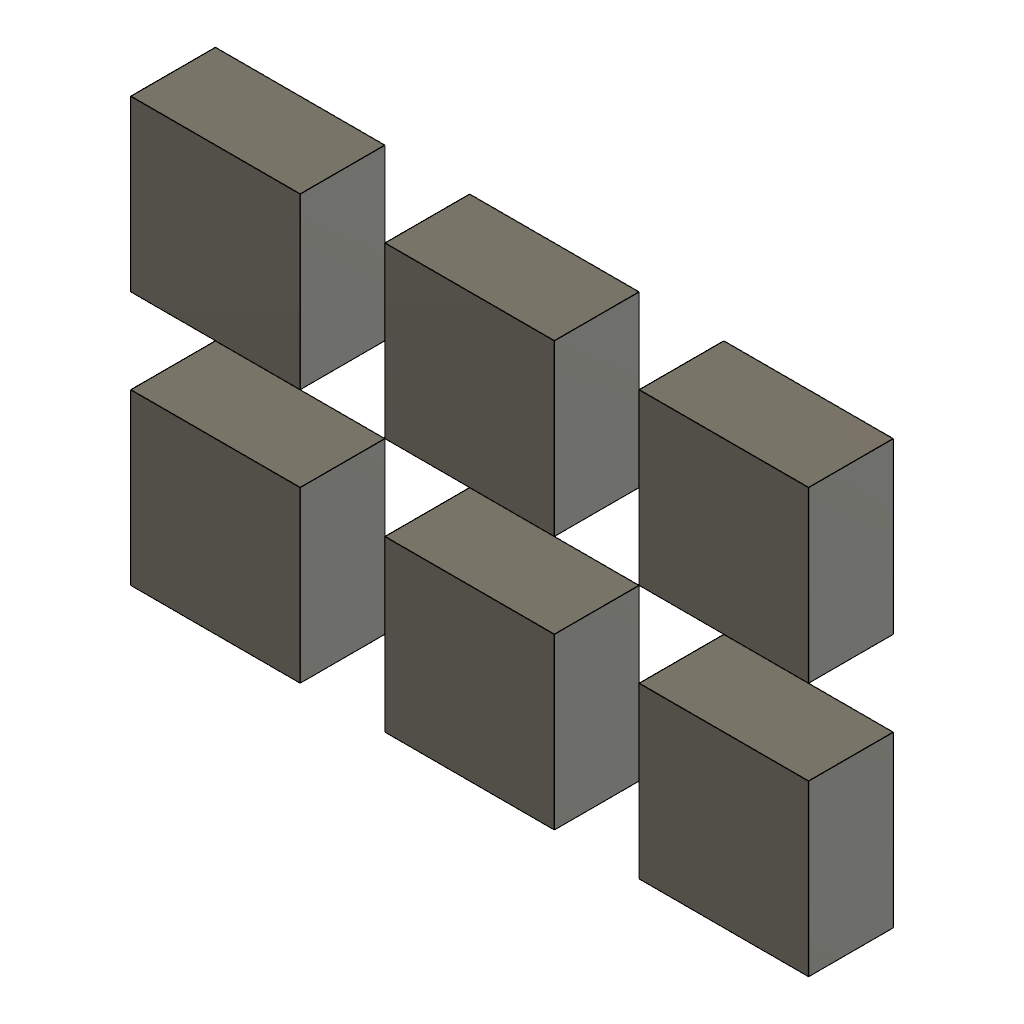
pat_rect_bodies (Autodesk Fusion 360 design; units mm, degrees)
part number: 2026-11-13-14-43-53-146
Autodesk Fusion 360 part; units mm, degrees
sketch "Sketch1" plane through (0, 0, 0) normal (0, 0, 1) x (1, 0, 0)
  line L0 (0, 0) -> (10, 0)
  line L1 (10, 0) -> (10, 10)
  line L2 (10, 10) -> (0, 10)
  line L3 (0, 10) -> (0, 0)
extrude "Extrude1" add sketch "Sketch1" along normal blind 5 makes body 1
pattern_linear "R-Pattern1" count 3 spacing 15 along (1, 0, 0) count 2 spacing 15 along (0, 1, 0) of bodies 1 makes body 2 at (18.3333, 6.6667, 0) makes body 3 at (33.3333, 6.6667, 0) makes body 4 at (3.3333, 21.6667, 0) makes body 5 at (18.3333, 21.6667, 0) makes body 6 at (33.3333, 21.6667, 0)
